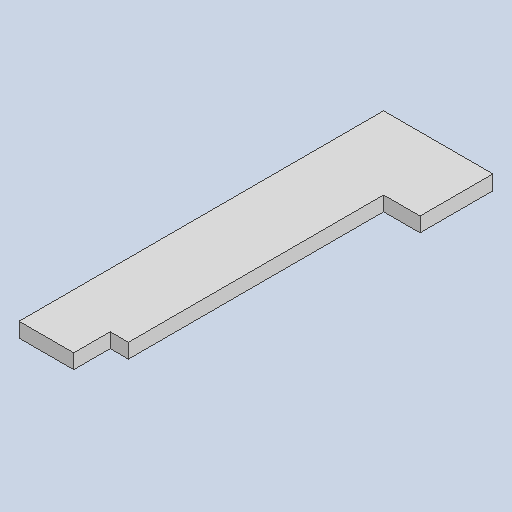
# Autodesk Inventor part: PRF-1005 Slab
Saved by Autodesk Inventor 2026.2 (Build 302298000, 298)
## iProperties
Created: 2026-10-18
Part Number: PRF-1005 Slab
Material: Generic
Description: Floor slab with 3 ledges, placed at +2100 in building asm
Document SubType Name: Modeling
Designer: admin
Stock Number: Перекрытие (антресоль) +2100…+2500
Density: 1 g/cm^3
Appearance: Default
Author: admin
Autodesk Inventor part; units mm, degrees
ref_plane "YZ Plane" through (0, 0, 0) normal (1, 0, 0) x (0, 1, 0)
ref_plane "XZ Plane" through (0, 0, 0) normal (0, 1, 0) x (-1, 0, 0)
ref_plane "XY Plane" through (0, 0, 0) normal (0, 0, 1) x (1, 0, 0)
sketch "Sketch1" plane through (0, 0, 0) normal (0, 1, 0) x (-1, 0, 0)
  line L0 (3000, 6000) -> (1500, 6000)
  line L1 (1500, 6000) -> (1500, 5000)
  line L2 (1500, 5000) -> (3000, 5000)
  line L3 (3000, 5000) -> (3000, 6000)
  line L4 (3000, 5000) -> (1000, 5000)
  line L5 (1000, 5000) -> (1000, -2000)
  line L6 (1000, -2000) -> (3000, -2000)
  line L7 (3000, -2000) -> (3000, 5000)
  line L8 (3000, -2000) -> (0, -2000)
  line L9 (0, -2000) -> (0, -4000)
  line L10 (0, -4000) -> (3000, -4000)
  line L11 (3000, -4000) -> (3000, -2000)
  constraints: 24 end point, 6 parallel, 3 horizontal, 3 perpendicular
extrude "Extrusion1" add sketch "Sketch1" along normal blind 400 contours L3 L2 L1 L0
extrude "Extrusion2" add sketch "Sketch1" along normal blind 400 contours L7 L6 L5 L4 L2
extrude "Extrusion3" add sketch "Sketch1" along normal blind 400 contours L11 L10 L9 L8 L6
equation "\"d0\" = Slab1005_Thickness"
equation "\"d2\" = Slab1005_Thickness"
equation "\"d4\" = Slab1005_Thickness"
equation "\"Slab1005_Thickness\" = 400"
body "Solid1"
